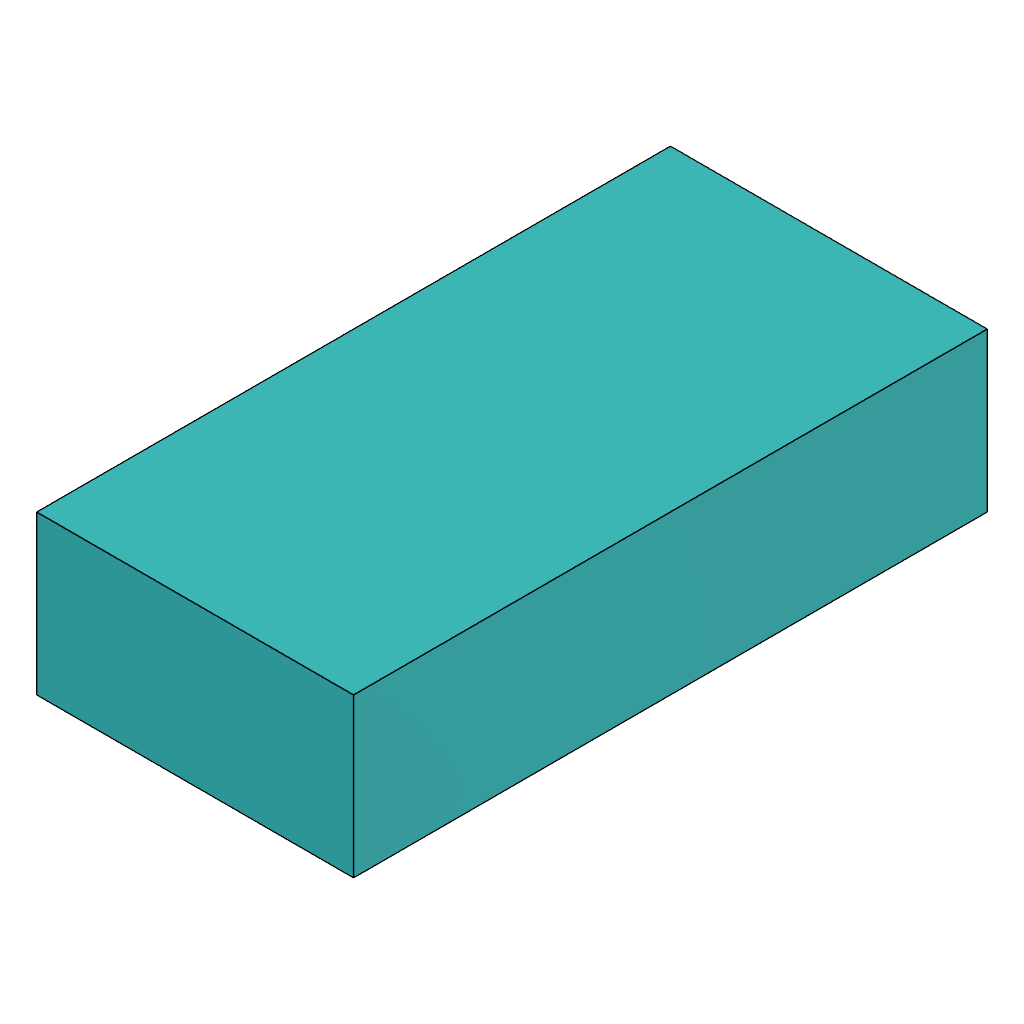
level -1 cuboid (Autodesk Fusion 360 design; units mm, degrees)
part number: 2026-10-11-11-04-22-949
Autodesk Fusion 360 part; units mm, degrees
box "BoxPrimitive1" add length 40 width 20 height 10 placed x (0, 0, -1) y (-1, 0, 0) z (0, 1, 0) at (0, 0, 0)
